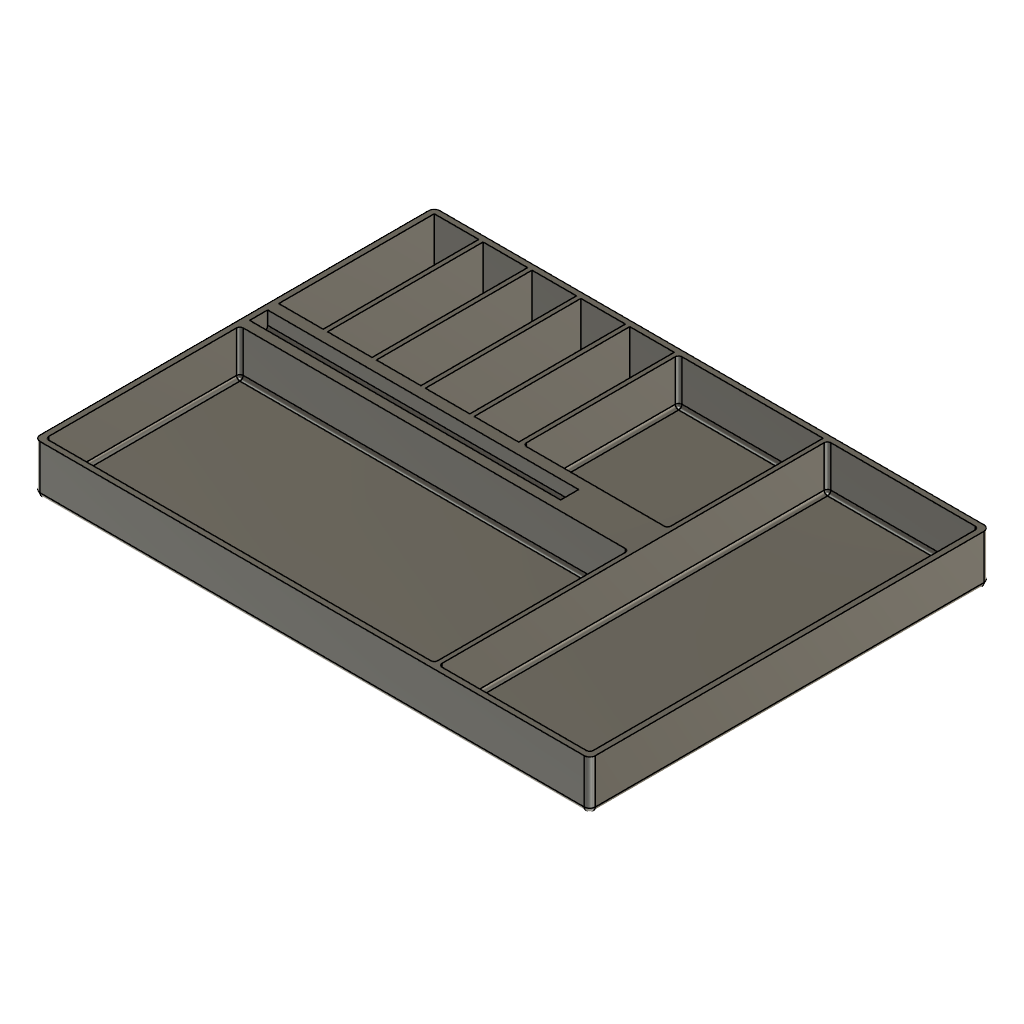
Toolbox (Autodesk Fusion 360 archive; units mm, degrees)
design "External2"
part number: 2026-10-17-18-14-28-487
Autodesk Fusion 360 part; units mm, degrees
derive "DerivedContext1"
sketch "sketch 247" plane through (0, 0, 2.5) normal (0, 0, 1) x (-1, 0, 0)
  line L0 (252.5, -2.5) -> (2.5, -2.5)
  line L1 (2.5, -2.5) -> (2.5, -182.5)
  line L2 (2.5, -182.5) -> (252.5, -182.5)
  line L3 (252.5, -182.5) -> (252.5, -2.5)
  line L4 (250, -180) -> (230, -180)
  line L5 (230, -180) -> (230, -110)
  line L6 (230, -110) -> (250, -110)
  line L7 (250, -110) -> (250, -180)
  line L8 (228, -180) -> (208, -180)
  line L9 (208, -180) -> (208, -110)
  line L10 (208, -110) -> (228, -110)
  line L11 (228, -110) -> (228, -180)
  line L12 (206, -180) -> (186, -180)
  line L13 (186, -180) -> (186, -110)
  line L14 (186, -110) -> (206, -110)
  line L15 (206, -110) -> (206, -180)
  line L16 (184, -180) -> (164, -180)
  line L17 (164, -180) -> (164, -110)
  line L18 (164, -110) -> (184, -110)
  line L19 (184, -110) -> (184, -180)
  line L20 (162, -180) -> (142, -180)
  line L21 (142, -180) -> (142, -110)
  line L22 (142, -110) -> (162, -110)
  line L23 (162, -110) -> (162, -180)
  line L24 (250, -105) -> (110, -105)
  line L25 (110, -105) -> (110, -97.4)
  line L26 (110, -97.4) -> (250, -97.4)
  line L27 (250, -97.4) -> (250, -105)
  line L28 (140, -180) -> (5, -180)
  line L29 (5, -180) -> (5, -110)
  line L30 (5, -110) -> (140, -110)
  line L31 (140, -110) -> (140, -180)
  line L32 (250, -92.5) -> (75, -92.5)
  line L33 (75, -92.5) -> (75, -5)
  line L34 (75, -5) -> (250, -5)
  line L35 (250, -5) -> (250, -92.5)
  line L36 (5, -5) -> (73, -5)
  line L37 (73, -5) -> (73, -108)
  line L38 (73, -108) -> (5, -108)
  line L39 (5, -108) -> (5, -5)
extrude "Extrude1" add sketch "sketch 247" along normal blind 20
extrude "Extrude2" add sketch "sketch 247" against normal blind 2.5 contours L0 L1 L2 L3 | L4 L5 L6 L7 | L8 L9 L10 L11 | L12 L13 L14 L15 | L16 L17 L18 L19 | L20 L21 L22 L23 | L24 L25 L26 L27 | L28 L29 L30 L31 | L32 L33 L34 L35 | L36 L37 L38 L39
extrude "Extrude3" add 1 faces at (-156.6667, 99.9333, 2.5) along direction (0, 0, 1) blind 12
fillet "Fillet1" radius 2.5 8 edges at (-127.5, 2.5, 0) (-252.5, 2.5, 11.25) (-252.5, 92.5, 0) (-252.5, 182.5, 11.25) (-127.5, 182.5, 0) (-2.5, 182.5, 11.25) (-2.5, 2.5, 11.25) (-2.5, 92.5, 0)
extrude "Extrude4" cut 1 faces at (-156.6667, 97.4, 17.1667) along direction (0, -1, 0) blind 0.5
fillet "Fillet2" radius 2 1 edges at (-180, 105, 14.5)
fillet "Fillet3" radius 2 1 edges at (-180, 96.9, 14.5)
extrude "Extrude5" add 1 faces at (-5, 156.6667, 9.1667) along direction (-1, 0, 0) blind 70
extrude "Extrude6" cut 1 faces at (-50.3333, 108, 9.1667) along direction (0, 1, 0) blind 72
fillet "Fillet4" radius 1.5 8 edges at (-250, 92.5, 12.5) (-162.5, 92.5, 2.5) (-250, 48.75, 2.5) (-162.5, 5, 2.5) (-250, 5, 12.5) (-75, 5, 12.5) (-75, 48.75, 2.5) (-75, 92.5, 12.5)
fillet "Fillet5" radius 1.5 15 edges at (-73, 180, 12.5) (-39, 180, 2.5) (-107.5, 180, 2.5) (-140, 180, 12.5) (-75, 145, 2.5) (-5, 92.5, 2.5) (-39, 5, 2.5) (-5, 5, 12.5) (-73, 92.5, 2.5) (-73, 5, 12.5) (-5, 180, 12.5) (-140, 110, 12.5) (-107.5, 110, 2.5) (-140, 145, 2.5) (-75, 110, 12.5)

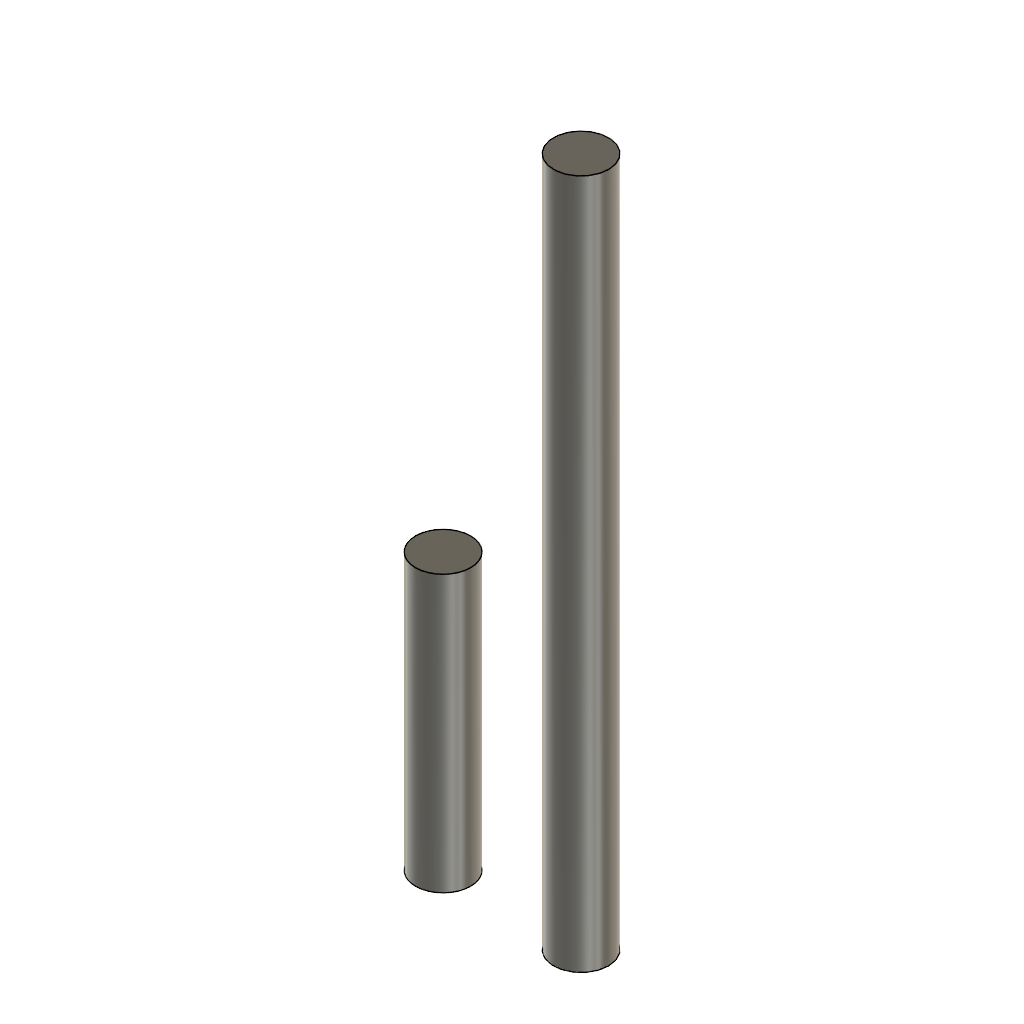
design "Dowels"
part number: 2026-10-19-10-37-24-881
Autodesk Fusion 360 part; units mm, degrees
cylinder "CylinderPrimitive1" add diameter 4 height 60 placed x (1, 0, 0) y (0, 1, 0) z (0, 0, 1) at (-10, 225, 0) makes body 1
cylinder "CylinderPrimitive2" add diameter 4 height 18 placed x (1, 0, 0) y (0, 1, 0) z (0, 0, 1) at (-20, 225, 0) separate body makes body 2
extrude "Extrude1" add 1 faces at (-20.5276, 226.2639, 18) along direction (0, 0, 1) blind 2 on bodies 2 bodies 2
extrude "Extrude2" cut 1 faces at (-10.5276, 226.2639, 60) along direction (0, 0, -1) blind 10 on bodies 1 bodies 1

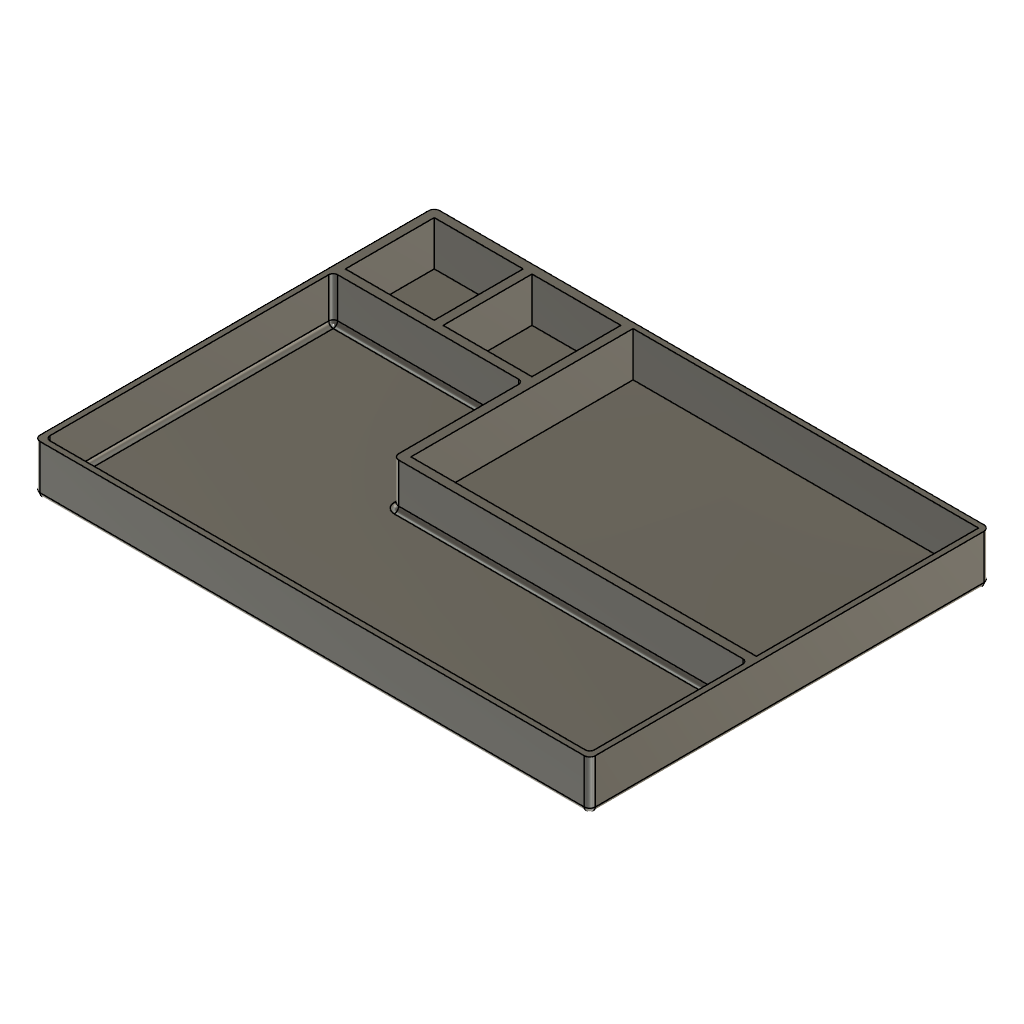
design "External3"
part number: 2026-10-18-22-53-54-016
Autodesk Fusion 360 part; units mm, degrees
derive "DerivedContext1"
sketch "sketch 525" plane through (0, 0, 2.5) normal (0, 0, 1) x (-1, 0, 0)
  line L0 (252.5, -2.5) -> (2.5, -2.5)
  line L1 (2.5, -2.5) -> (2.5, -182.5)
  line L2 (2.5, -182.5) -> (252.5, -182.5)
  line L3 (252.5, -182.5) -> (252.5, -2.5)
  line L4 (5, -5) -> (250, -5)
  line L5 (5, -180) -> (5, -80)
  line L6 (5, -76) -> (5, -5)
  line L7 (250, -180) -> (210, -180)
  line L8 (210, -180) -> (210, -140)
  line L9 (210, -140) -> (250, -140)
  line L10 (250, -5) -> (250, -136)
  line L11 (250, -140) -> (250, -180)
  line L12 (206, -180) -> (166, -180)
  line L13 (166, -180) -> (166, -140)
  line L14 (166, -140) -> (206, -140)
  line L15 (206, -140) -> (206, -180)
  line L16 (206, -180) -> (166, -180)
  line L17 (162, -180) -> (5, -180)
  line L18 (250, -136) -> (166, -136)
  line L19 (162, -180) -> (162, -80)
  line L20 (5, -80) -> (162, -80)
  line L21 (166, -136) -> (166, -76)
  line L22 (166, -76) -> (5, -76)
extrude "Extrude1" add sketch "sketch 525" along normal blind 15
extrude "Extrude2" add sketch "sketch 525" against normal blind 2.5 contours L0 L1 L2 L3 | L4 L6 L10 L18 L21 L22 | L5 L17 L19 L20 | L7 L8 L9 L11 | L12 L13 L14 L15 L16
fillet "Fillet1" radius 2.5 8 edges at (-252.5, 2.5, 8.75) (-252.5, 182.5, 8.75) (-252.5, 92.5, 0) (-127.5, 182.5, 0) (-2.5, 182.5, 8.75) (-2.5, 92.5, 0) (-2.5, 2.5, 8.75) (-127.5, 2.5, 0)
extrude "Extrude3" add 1 faces at (-192.6667, 180, 12.5) along direction (0, -1, 0) blind 1.5
extrude "Extrude4" add 1 faces at (-236.6667, 180, 12.5) along direction (0, -1, 0) blind 1.5
extrude "Extrude5" add 1 faces at (-222, 136, 7.5) along direction (0, -1, 0) blind 1.5
extrude "Extrude6" cut 1 faces at (-179.3333, 140, 12.5) along direction (0, -1, 0) blind 1.5
extrude "Extrude7" cut 1 faces at (-223.3333, 140, 12.5) along direction (0, -1, 0) blind 1.5
extrude "Extrude8" add 1 faces at (-250, 151.8333, 12.5) along direction (1, 0, 0) blind 1.5
extrude "Extrude9" add 1 faces at (-206, 151.8333, 12.5) along direction (1, 0, 0) blind 1.5
extrude "Extrude10" cut 1 faces at (-210, 151.8333, 7.5) along direction (1, 0, 0) blind 1.5
extrude "Extrude11" cut 1 faces at (-166, 151.8333, 7.5) along direction (1, 0, 0) blind 1.5
extrude "Extrude12" add 1 faces at (-162, 146.6667, 7.5) along direction (1, 0, 0) blind 1.5
extrude "Extrude13" cut 1 faces at (-166, 115, 12.5) along direction (1, 0, 0) blind 1.5
fillet "Fillet2" radius 2.5 1 edges at (-164.5, 76, 10)
fillet "Fillet3" radius 2 12 edges at (-250, 134.5, 10) (-207.25, 134.5, 2.5) (-164.5, 134.5, 10) (-83.5, 76, 2.5) (-163.7678, 76.7322, 2.5) (-164.5, 106.5, 2.5) (-5, 76, 10) (-127.5, 5, 2.5) (-5, 40.5, 2.5) (-5, 5, 10) (-250, 5, 10) (-250, 69.75, 2.5)
move_body "Move1" bodies 1 to x (1, 0, 0) y (0, 1, 0) z (0, 0, 1) at (0, 0, 22.5)
extrude "Extrude14" add 1 faces at (-161.8333, 130.8333, 40) along direction (0, 0, 1) blind 5
